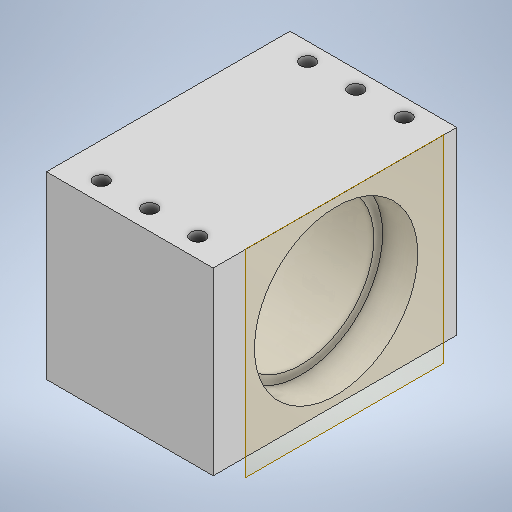
# Autodesk Inventor part: 内端舵机支架
Saved by Autodesk Inventor 2025 (Build 290162000, 162)
## iProperties
Created: 2026-11-07
Part Number: 内端舵机支架
Material: 常规
Document SubType Name: Modeling
Designer: ylh00
Mass: 27.0698 g
Surface Area: 117.337 cm^2
Volume: 27.0698 cm^3
Density: 1 g/cm^3
Appearance: 默认
Author: ylh00
Autodesk Inventor part; units mm, degrees
ref_plane "YZ Plane" through (0, 0, 0) normal (1, 0, 0) x (0, 1, 0)
ref_plane "XZ Plane" through (0, 0, 0) normal (0, 1, 0) x (-1, 0, 0)
sketch "草图1" plane through (0, 0, 0) normal (1, 0, 0) x (0, 1, 0)
  circle A0 centre (0, 0) radius 18.6
  circle A1 centre (0, 0) radius 20.5
  dimension "d0" = 37.2
  dimension "d1" = 41
  constraints: 2 centre point, 2 coincident
  measures "d0" diameter of A0
  measures "d1" diameter of A1
extrude "拉伸1" add sketch "草图1" along normal blind 37
ref_plane "工作平面1" through (30, 0, 0) normal (1, 0, 0) x (0, 0, -1)
sketch "草图2" plane through (30, 0, 0) normal (1, 0, 0) x (0, 0, -1)
  circle A0 centre (0, 0) radius 16.6
  circle A1 centre (0, 0) radius 18.6
  dimension "d5" = 33.2
  constraints: 2 centre point, 2 coincident
  measures "d5" diameter of A0
extrude "拉伸2" add sketch "草图2" against normal blind 23
ref_plane "工作平面2" through (40, 0, 0) normal (1, 0, 0) x (0, 0, -1)
sketch "草图3" plane through (0, 0, 0) normal (-1, 0, 0) x (0, 0, 1)
  line L0 (-20.5, -20.5) -> (-20.5, 20.5)
  line L1 (-20.5, 20.5) -> (20.5, 20.5)
  line L2 (20.5, 20.5) -> (20.5, -20.5)
  line L3 (20.5, -20.5) -> (-20.5, -20.5)
  line L4 (-20.5, -20.5) -> (20.5, 20.5) construction
  line L5 (-20.5, 20.5) -> (20.5, -20.5) construction
  circle A0 centre (0, 0) radius 20.5
  point P0 (-20.5, 0)
  point P1 (0, 20.5)
  point P2 (20.5, 0)
  point P3 (0, -20.5)
  constraints: 12 end point, 2 midpoint, 2 parallel, 1 centre point, 1 coincident, 1 perpendicular, 1 tangent, 1 vertical
extrude "拉伸3" add sketch "草图3" against normal up to surface (37 mm away) contours L0 A0 L3 | L0 L1 A0 | A0 L2 L3 | L1 L2 A0
thicken "加厚1" operation add thickness 1 both sides no extend neighbours no toward (1, 0, 0) faces at (37, 0.7473, 19.8215)
sketch "草图7" plane through (0, 20.5, 20.5) normal (0, 1, 0) x (1, 0, 0)
  line L0 (0, 41) -> (38, 41)
  line L1 (38, 41) -> (38, 48)
  line L2 (38, 48) -> (0, 48)
  line L3 (0, 48) -> (0, 41)
  line L4 (0, 41) -> (0, 0) projected
  line L5 (0, 0) -> (38, 0)
  line L6 (38, 0) -> (38, -7.5)
  line L7 (38, -7.5) -> (0, -7.5)
  line L8 (0, -7.5) -> (0, 0)
  line L9 (0, 20.5) -> (38, 20.5)
  line L10 (38, 41) -> (38, 0) projected
  circle A0 centre (19, 44) radius 1.65
  circle A1 centre (8, 44) radius 1.65
  circle A2 centre (30, 44) radius 1.65
  circle A3 centre (19, -3) radius 1.65
  circle A4 centre (8, -3) radius 1.65
  circle A5 centre (30, -3) radius 1.65
  dimension "d21" = 7
  dimension "d22" = 7.5
  constraints: 18 end point, 6 centre point, 4 parallel, 3 symmetric about line, 2 horizontal, 2 perpendicular, 1 midpoint, 1 point on line, 3 other
  measures "d21" distance of L1.end L0.end
  measures "d22" distance of L5.end L6.end
extrude "拉伸6" add sketch "草图7" against normal up to surface (41 mm away) contours L3 L2 L1 L0 | L5 L6 L7 L8
